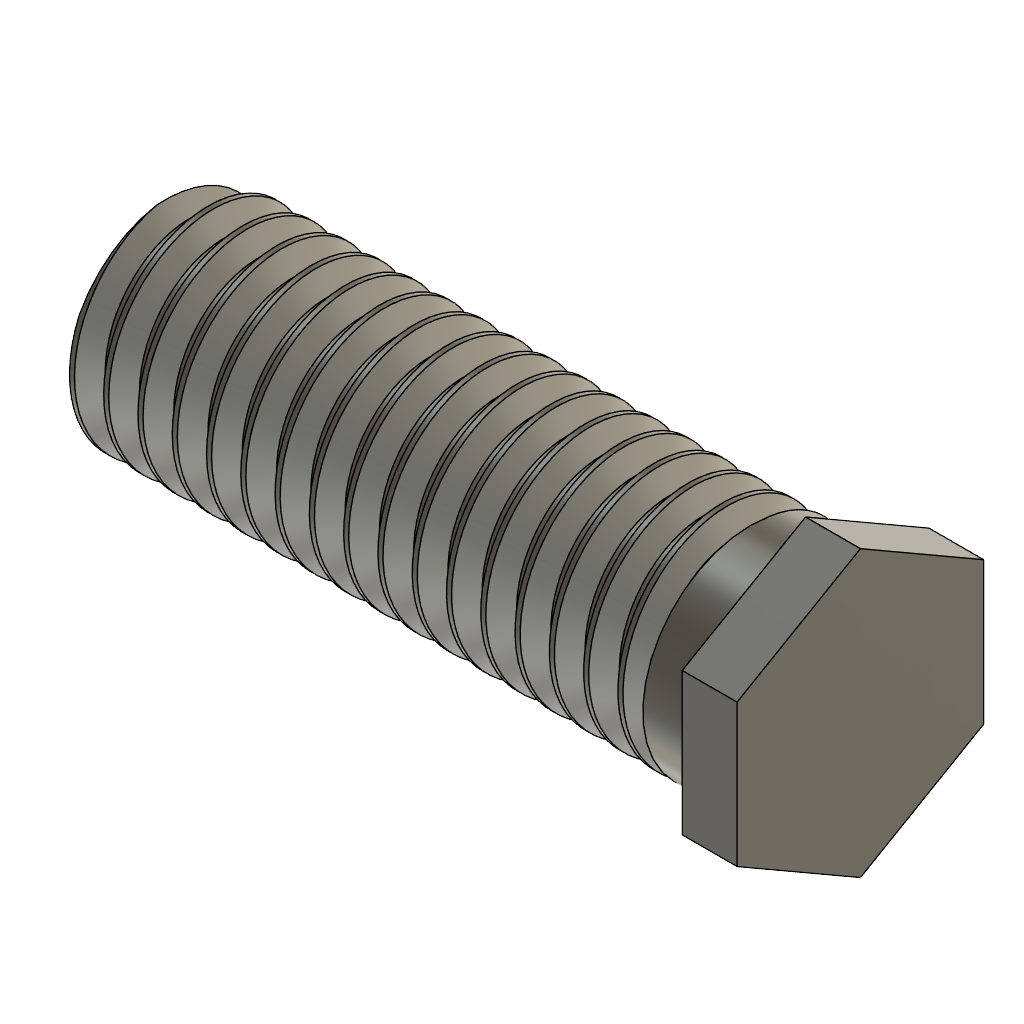
screw_1_nozzle (Autodesk Fusion 360 design; units mm, degrees)
part number: 2026-11-21-14-55-43-020
Autodesk Fusion 360 part; units mm, degrees
sketch "Sketch1" plane through (0, 0, 0) normal (1, 0, 0) x (0, 1, 0)
  circle A0 centre (0, 0) radius 4
  line L0 (-4.4985, 2.5972) -> (-4.4985, -2.5972)
  line L1 (-4.4985, -2.5972) -> (0, -5.1944)
  line L2 (0, -5.1944) -> (4.4985, -2.5972)
  line L3 (4.4985, -2.5972) -> (4.4985, 2.5972)
  line L4 (4.4985, 2.5972) -> (0, 5.1944)
  line L5 (0, 5.1944) -> (-4.4985, 2.5972)
  constraint coincident A0.centre origin
extrude "Extrude1" add sketch "Sketch1" against normal blind 25 contours A0
extrude "Extrude2" add sketch "Sketch1" against normal blind 2
thread "Thread1" "ISO Metric profile 8.0 M8x1.25 M8x1.25 6g" major diameter 7.866 minor diameter 6.4455 pitch 1.25 angle 60 modelled right hand crest width 0.1833 on face at (-9.6667, 3.9801, -0.3983) from (-4, 0, 0) to (-25, 0, 0) crest through (-1.6875, 3.933, 0)
